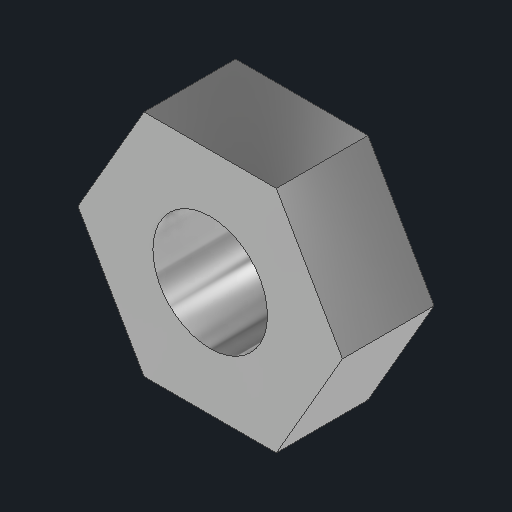
# Autodesk Inventor part: nut_M2.5
Saved by Autodesk Inventor 2027.1 (Build 311270010, 270A)
## iProperties
Created: 2026-11-09
Part Number: nut_M2.5
Material: Generic
Description: Hex nut M2.5 ISO 4032 (5 AF, 2 thick)
Document SubType Name: Modeling
Designer: alexg
Density: 1 g/cm^3
Appearance: Stainless Steel - Bright
Author: alexg
Autodesk Inventor part; units mm, degrees
ref_plane "YZ Plane" through (0, 0, 0) normal (1, 0, 0) x (0, 1, 0)
ref_plane "XZ Plane" through (0, 0, 0) normal (0, 1, 0) x (-1, 0, 0)
ref_plane "XY Plane" through (0, 0, 0) normal (0, 0, 1) x (1, 0, 0)
sketch "Hex sketch" plane through (0, 0, 0) normal (0, 0, 1) x (1, 0, 0)
  line L0 (2.8868, 0) -> (1.4434, 2.5)
  line L1 (1.4434, 2.5) -> (-1.4434, 2.5)
  line L2 (-1.4434, 2.5) -> (-2.8868, 0)
  line L3 (-2.8868, 0) -> (-1.4434, -2.5)
  line L4 (-1.4434, -2.5) -> (1.4434, -2.5)
  line L5 (1.4434, -2.5) -> (2.8868, 0)
  constraints: 12 end point
extrude "Hex" add sketch "Hex sketch" along normal blind 2
sketch "Thread bore sketch" plane through (0, 0, 0) normal (0, 0, 1) x (1, 0, 0)
  circle A0 centre (0, 0) radius 1.25
  constraints: 1 centre point
extrude "Thread bore" cut sketch "Thread bore sketch" along normal blind 2
body "Solid1"
